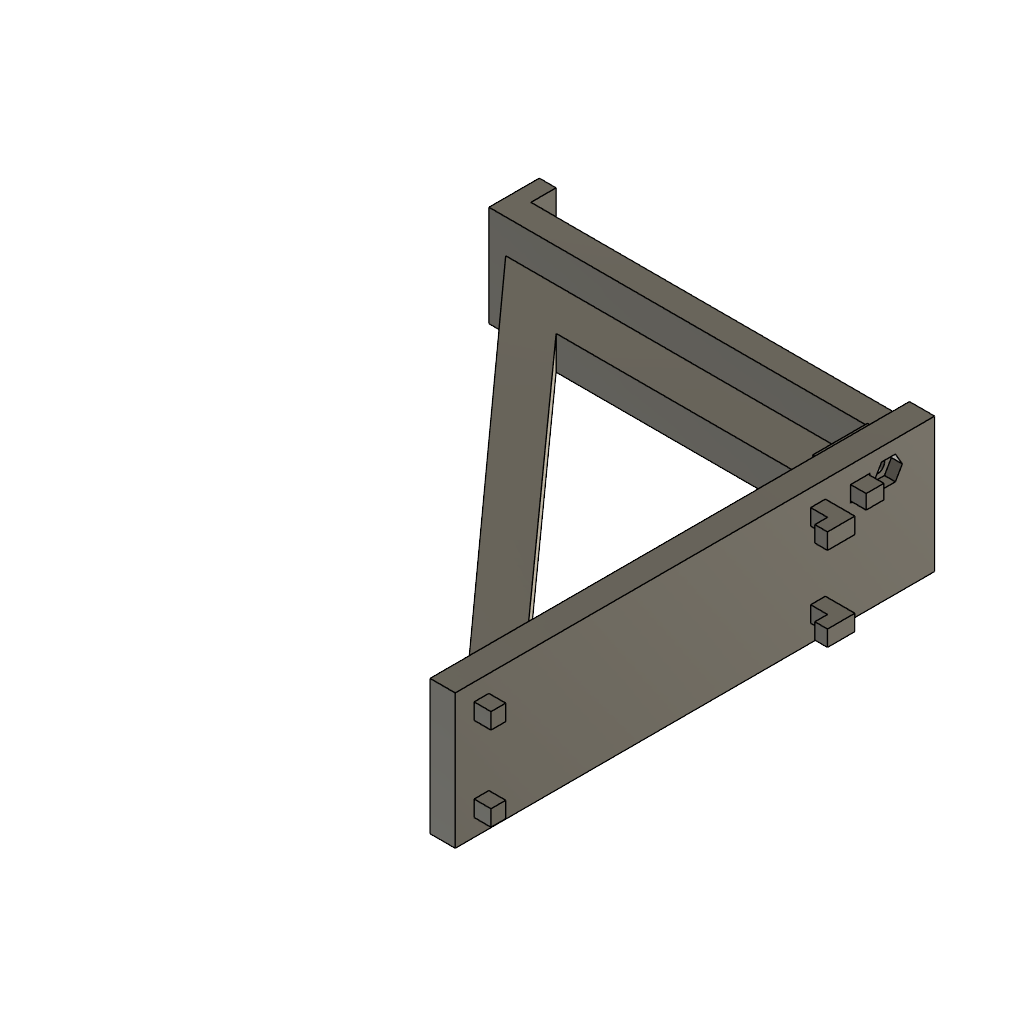
Single_Bracket_v04 (Autodesk Fusion 360 design; units mm, degrees)
part number: 2026-10-19-08-04-38-137
part number: 2026-10-19-08-04-38-454
part number: 2026-10-19-08-04-40-457
part number: 2026-10-19-08-04-41-240
Autodesk Fusion 360 part; units mm, degrees
ref_plane "工作平面1" through (0, 0, -16) normal (0, 0, 1) x (1, 0, 0) in component "Single bracket V04 - THROAT 4.0 - UNRATED"
sketch "草图1" plane through (0, 0, -16) normal (0, 0, 1) x (1, 0, 0) in component "Single bracket V04 - THROAT 4.0 - UNRATED"
  line L0 (-6, -108) -> (0, -108)
  line L1 (0, -108) -> (0, 6)
  line L2 (0, 6) -> (-6, 6)
  line L3 (-6, 6) -> (-6, -108)
extrude "Backplate 6 mm" add sketch "草图1" along normal blind 32 makes body 1 in component "Single bracket V04 - THROAT 4.0 - UNRATED"
ref_plane "工作平面2" through (0, 0, -12) normal (0, 0, 1) x (1, 0, 0) in component "Single bracket V04 - THROAT 4.0 - UNRATED"
sketch "草图2" plane through (0, 0, -12) normal (0, 0, 1) x (1, 0, 0) in component "Single bracket V04 - THROAT 4.0 - UNRATED"
  line L0 (-98, 0) -> (-6, 0)
  line L1 (-6, 0) -> (-6, 6)
  line L2 (-6, 6) -> (-98, 6)
  line L3 (-98, 6) -> (-98, 0)
extrude "Shelf 92 mm" add sketch "草图2" along normal blind 24 bodies 1 in component "Single bracket V04 - THROAT 4.0 - UNRATED"
ref_plane "工作平面3" through (0, 0, -4) normal (0, 0, 1) x (1, 0, 0) in component "Single bracket V04 - THROAT 4.0 - UNRATED"
sketch "草图3" plane through (0, 0, -4) normal (0, 0, 1) x (1, 0, 0) in component "Single bracket V04 - THROAT 4.0 - UNRATED"
  line L0 (-6, -100) -> (-6, 0)
  line L1 (-6, 0) -> (-96, 0)
  line L2 (-96, 0) -> (-6, -100)
extrude "Central triangular web 8 mm" add sketch "草图3" along normal blind 8 bodies 1 in component "Single bracket V04 - THROAT 4.0 - UNRATED"
ref_plane "工作平面4" through (0, 0, -4) normal (0, 0, 1) x (1, 0, 0) in component "Single bracket V04 - THROAT 4.0 - UNRATED"
sketch "草图4" plane through (0, 0, -4) normal (0, 0, 1) x (1, 0, 0) in component "Single bracket V04 - THROAT 4.0 - UNRATED"
  line L0 (-14, -77) -> (-14, -10)
  line L1 (-14, -10) -> (-74, -10)
  line L2 (-74, -10) -> (-14, -77)
extrude "Web lightening window" cut sketch "草图4" along normal blind 8 bodies 1 in component "Single bracket V04 - THROAT 4.0 - UNRATED"
ref_plane "工作平面5" through (0, 0, -12) normal (0, 0, 1) x (1, 0, 0) in component "Single bracket V04 - THROAT 4.0 - UNRATED"
sketch "草图5" plane through (0, 0, -12) normal (0, 0, 1) x (1, 0, 0) in component "Single bracket V04 - THROAT 4.0 - UNRATED"
  line L0 (-100, 0) -> (-96, 0)
  line L1 (-96, 0) -> (-96, 12)
  line L2 (-96, 12) -> (-100, 12)
  line L3 (-100, 12) -> (-100, 0)
extrude "Front stop 6 mm above shelf" add sketch "草图5" along normal blind 24 bodies 1 in component "Single bracket V04 - THROAT 4.0 - UNRATED"
ref_plane "工作平面6" through (0, 0, -11.9) normal (0, 0, 1) x (1, 0, 0) in component "Single bracket V04 - THROAT 4.0 - UNRATED"
sketch "草图6" plane through (0, 0, -11.9) normal (0, 0, 1) x (1, 0, 0) in component "Single bracket V04 - THROAT 4.0 - UNRATED"
  line L0 (0, -23.5) -> (4, -23.5)
  line L1 (4, -23.5) -> (4, -26.5)
  line L2 (4, -26.5) -> (7, -26.5)
  line L3 (7, -26.5) -> (7, -20)
  line L4 (7, -20) -> (0, -20)
  line L5 (0, -20) -> (0, -23.5)
extrude "Upper hook throat 4.0" add sketch "草图6" along normal blind 3.8 bodies 1 in component "Single bracket V04 - THROAT 4.0 - UNRATED"
ref_plane "工作平面7" through (0, 0, -11.9) normal (0, 0, 1) x (1, 0, 0) in component "Single bracket V04 - THROAT 4.0 - UNRATED"
sketch "草图7" plane through (0, 0, -11.9) normal (0, 0, 1) x (1, 0, 0) in component "Single bracket V04 - THROAT 4.0 - UNRATED"
  line L0 (0, -103.5) -> (4, -103.5)
  line L1 (4, -103.5) -> (4, -100)
  line L2 (4, -100) -> (0, -100)
  line L3 (0, -100) -> (0, -103.5)
extrude "Lower locating tab" add sketch "草图7" along normal blind 3.8 bodies 1 in component "Single bracket V04 - THROAT 4.0 - UNRATED"
ref_plane "工作平面8" through (0, 0, 8.1) normal (0, 0, 1) x (1, 0, 0) in component "Single bracket V04 - THROAT 4.0 - UNRATED"
sketch "草图8" plane through (0, 0, 8.1) normal (0, 0, 1) x (1, 0, 0) in component "Single bracket V04 - THROAT 4.0 - UNRATED"
  line L0 (0, -23.5) -> (4, -23.5)
  line L1 (4, -23.5) -> (4, -26.5)
  line L2 (4, -26.5) -> (7, -26.5)
  line L3 (7, -26.5) -> (7, -20)
  line L4 (7, -20) -> (0, -20)
  line L5 (0, -20) -> (0, -23.5)
extrude "Upper hook throat 4.0 (1)" add sketch "草图8" along normal blind 3.8 bodies 1 in component "Single bracket V04 - THROAT 4.0 - UNRATED"
ref_plane "工作平面9" through (0, 0, 8.1) normal (0, 0, 1) x (1, 0, 0) in component "Single bracket V04 - THROAT 4.0 - UNRATED"
sketch "草图9" plane through (0, 0, 8.1) normal (0, 0, 1) x (1, 0, 0) in component "Single bracket V04 - THROAT 4.0 - UNRATED"
  line L0 (0, -103.5) -> (4, -103.5)
  line L1 (4, -103.5) -> (4, -100)
  line L2 (4, -100) -> (0, -100)
  line L3 (0, -100) -> (0, -103.5)
extrude "Lower locating tab (1)" add sketch "草图9" along normal blind 3.8 bodies 1 in component "Single bracket V04 - THROAT 4.0 - UNRATED"
ref_plane "工作平面10" through (0, 0, 8.1) normal (0, 0, 1) x (1, 0, 0) in component "Single bracket V04 - THROAT 4.0 - UNRATED"
sketch "草图10" plane through (0, 0, 8.1) normal (0, 0, 1) x (1, 0, 0) in component "Single bracket V04 - THROAT 4.0 - UNRATED"
  line L0 (-6, -14) -> (0, -14)
  line L1 (0, -14) -> (0, -9.4)
  line L2 (0, -9.4) -> (-6, -9.4)
  line L3 (-6, -9.4) -> (-6, -14)
extrude "Key guide opening" cut sketch "草图10" along normal blind 3.8 bodies 1 in component "Single bracket V04 - THROAT 4.0 - UNRATED"
ref_plane "工作平面11" through (-6, 0, 0) normal (1, 0, 0) x (0, 1, 0) in component "Single bracket V04 - THROAT 4.0 - UNRATED"
sketch "草图11" plane through (-6, 0, 0) normal (1, 0, 0) x (0, 0, -1) in component "Single bracket V04 - THROAT 4.0 - UNRATED"
  circle A0 centre (-10, -5) radius 1.7
extrude "M3 screw clearance" cut sketch "草图11" along normal blind 6 bodies 1 in component "Single bracket V04 - THROAT 4.0 - UNRATED"
ref_plane "工作平面12" through (-2.6, 0, 0) normal (1, 0, 0) x (0, 1, 0) in component "Single bracket V04 - THROAT 4.0 - UNRATED"
sketch "草图12" plane through (-2.6, 0, 0) normal (1, 0, 0) x (0, 0, -1) in component "Single bracket V04 - THROAT 4.0 - UNRATED"
  line L0 (-10, -1.7091) -> (-12.85, -3.3546)
  line L1 (-12.85, -3.3546) -> (-12.85, -6.6454)
  line L2 (-12.85, -6.6454) -> (-10, -8.2909)
  line L3 (-10, -8.2909) -> (-7.15, -6.6454)
  line L4 (-7.15, -6.6454) -> (-7.15, -3.3546)
  line L5 (-7.15, -3.3546) -> (-10, -1.7091)
extrude "Rear captive M3 nut pocket AF5.7 depth2.6" cut sketch "草图12" along normal blind 2.6 bodies 1 in component "Single bracket V04 - THROAT 4.0 - UNRATED"
ref_plane "工作平面1" through (0, 0, 5.5) normal (0, 0, 1) x (1, 0, 0) in component "Removable anti-lift key - M3 retained - TEST FIT"
sketch "草图1 (2)" plane through (0, 0, 5.5) normal (0, 0, 1) x (1, 0, 0) in component "Removable anti-lift key - M3 retained - TEST FIT"
  line L0 (-8, -15) -> (-6, -15)
  line L1 (-6, -15) -> (-6, -2)
  line L2 (-6, -2) -> (-8, -2)
  line L3 (-8, -2) -> (-8, -15)
extrude "Key flange 2 mm" add sketch "草图1 (2)" along normal blind 9 separate body makes body 2 in component "Removable anti-lift key - M3 retained - TEST FIT"
ref_plane "工作平面2" through (0, 0, 8.3) normal (0, 0, 1) x (1, 0, 0) in component "Removable anti-lift key - M3 retained - TEST FIT"
sketch "草图2 (2)" plane through (0, 0, 8.3) normal (0, 0, 1) x (1, 0, 0) in component "Removable anti-lift key - M3 retained - TEST FIT"
  line L0 (-6, -13.8) -> (3.5, -13.8)
  line L1 (3.5, -13.8) -> (3.5, -9.6)
  line L2 (3.5, -9.6) -> (-6, -9.6)
  line L3 (-6, -9.6) -> (-6, -13.8)
extrude "Key tongue" add sketch "草图2 (2)" along normal blind 3.4 bodies 2 in component "Removable anti-lift key - M3 retained - TEST FIT"
ref_plane "工作平面3" through (-8, 0, 0) normal (1, 0, 0) x (0, 1, 0) in component "Removable anti-lift key - M3 retained - TEST FIT"
sketch "草图3 (2)" plane through (-8, 0, 0) normal (1, 0, 0) x (0, 0, -1) in component "Removable anti-lift key - M3 retained - TEST FIT"
  circle A0 centre (-10, -5) radius 1.7
extrude "M3 key retainer clearance" cut sketch "草图3 (2)" along normal blind 2 bodies 2 in component "Removable anti-lift key - M3 retained - TEST FIT"
ref_plane "工作平面1" through (0, 0, -70) normal (0, 0, 1) x (1, 0, 0) in component "PSU reference only - NOT FOR PRINT"
sketch "草图1 (3)" plane through (0, 0, -70) normal (0, 0, 1) x (1, 0, 0) in component "PSU reference only - NOT FOR PRINT"
  line L0 (-94, 6) -> (-8, 6)
  line L1 (-8, 6) -> (-8, 156)
  line L2 (-8, 156) -> (-94, 156)
  line L3 (-94, 156) -> (-94, 6)
extrude "PSU 140 x 150 x 86" add sketch "草图1 (3)" along normal blind 140 separate body makes body 3 in component "PSU reference only - NOT FOR PRINT"
component "Single bracket V04 - THROAT 4.0 - UNRATED" placed x (1, 0, 0) y (0, 1, 0) z (0, 0, 1) at (0, 0, 0)
component "Removable anti-lift key - M3 retained - TEST FIT" placed x (1, 0, 0) y (0, 1, 0) z (0, 0, 1) at (0, 0, 0)
component "PSU reference only - NOT FOR PRINT" placed x (1, 0, 0) y (0, 1, 0) z (0, 0, 1) at (0, 0, 0)
